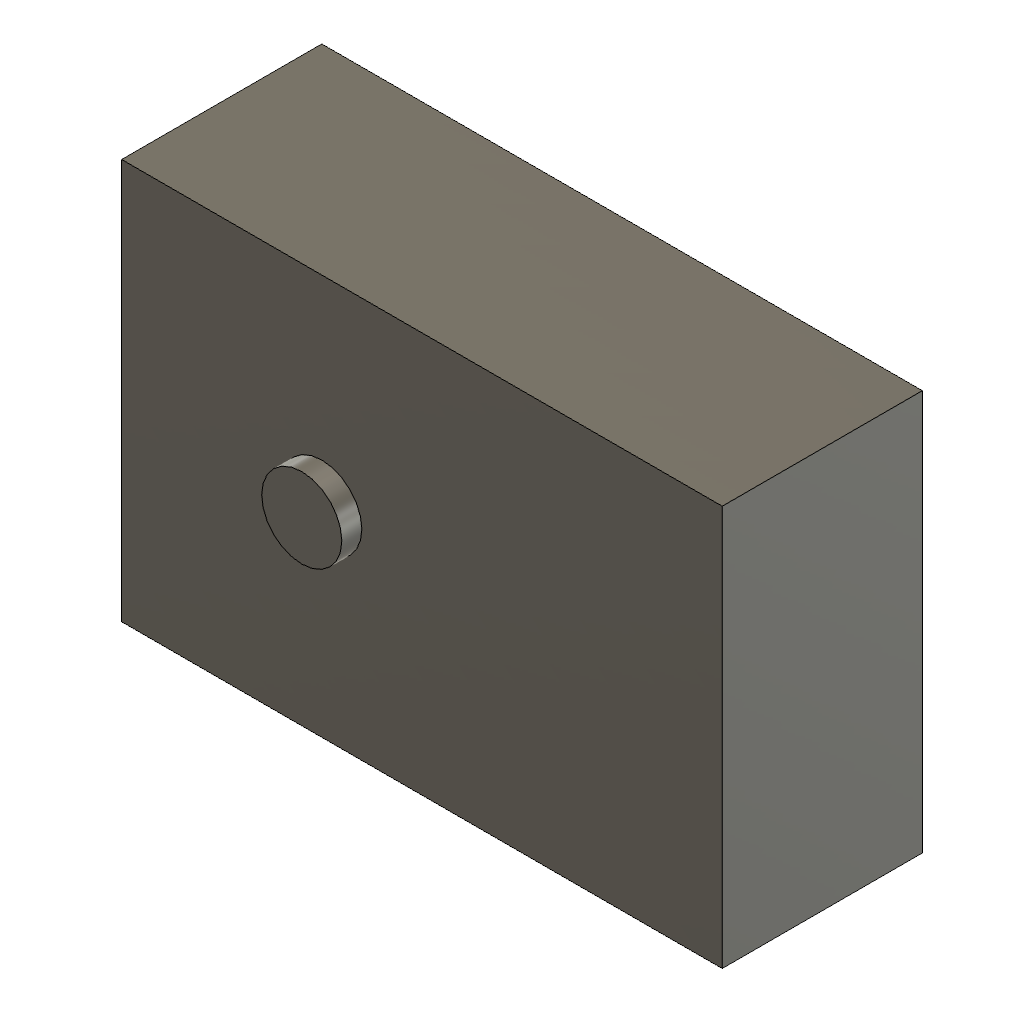
raised (Autodesk Fusion 360 design; units mm, degrees)
part number: 2026-10-20-21-02-23-001
Autodesk Fusion 360 part; units mm, degrees
sketch "Sketch1" plane through (0, 0, 0) normal (0, 0, 1) x (1, 0, 0)
  line L0 (0, 0) -> (60, 0)
  line L1 (60, 0) -> (60, 40)
  line L2 (60, 40) -> (0, 40)
  line L3 (0, 40) -> (0, 0)
extrude "Extrude1" add sketch "Sketch1" along normal blind 20
ref_plane "WorkPlane1" through (0, 0, 25) normal (0, 0, 1) x (1, 0, 0)
sketch "EmbossProfiles" plane through (0, 0, 25) normal (0, 0, 1) x (1, 0, 0)
  circle A0 centre (20, 20) radius 4
emboss "ProbeEmboss" depth 2 profiles "EmbossProfiles" section 1 onto face at (20, 26.6667, 20)
named bodies: "TargetPart"
